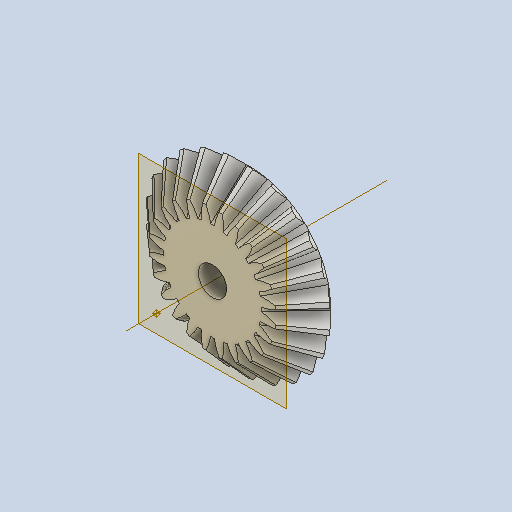
# Autodesk Inventor part: Bevel Gear1
Saved by Autodesk Inventor 2026.3 (Build 303398000, 398)
## iProperties
CustomPartVersion: 1
Created: 2026-10-19
Part Number: Bevel Gear1
Material: Steel, Mild
Document SubType Name: Modeling
Designer: Salim
Categories: <?xml version="1.0" encoding="UTF-16"?> <MemberInstance><Categories><FamilyTemplate><FamilyTemplateParameter ValueType="xs:double" Id="1" ObjectReferenceKey="da_z" ObjectType="kUserParameterObject"/><FamilyTemplateParameter ValueType="xs:double" Id="2" ObjectReferenceKey="da_b" ObjectType="kUserParameterObject"/><FamilyTemplateParameter ValueType="xs:double" Id="3" ObjectReferenceKey="da_beta" ObjectType="kUserParameterObject"/><FamilyTemplateParameter ValueType="xs:double" Id="4" ObjectReferenceKey="da_dae" ObjectType="kUserParameterObject"/><FamilyTemplateParameter ValueType="xs:double" Id="5" ObjectReferenceKey="da_ve" ObjectType="kUserParameterObject"/><FamilyTemplateParameter ValueType="xs:double" Id="6" ObjectReferenceKey="da_omega" ObjectType="kUserParameterObject"/><FamilyTemplateParameter ValueType="xs:string" Id="7" ObjectReferenceKey="EAIAABAAAAAAHwAAAAAAAIAAAAAAAAAA" ObjectType="83914240" SubObjectId="SurfaceGeometry"/></FamilyTemplate><ParamToTemplateMap><ParamToTemplate CategoryParameter="//CategoryParameter[@InternalName='046C89C9-8512-4d59-83FE-43B91F4F132A']" TemplateParameter="1"/><ParamToTemplate CategoryParameter="//CategoryParameter[@InternalName='2552DF32-E462-4b46-AEBF-C6C7768E72AC']" TemplateParameter="2"/><ParamToTemplate CategoryParameter="//CategoryParameter[@InternalName='C9EE641D-15FC-4fae-A226-E94C4372FDD7']" TemplateParameter="3"/><ParamToTemplate><ParamToTemplate CategoryParameter="//CategoryParameter[@InternalName='00B6519A-459B-49c7-AD84-2E56D39A5744']" ConstantValue="0.000000"/></ParamToTemplate><ParamToTemplate><ParamToTemplate CategoryParameter="//CategoryParameter[@InternalName='04B31F0E-C7A6-4894-AA32-9629BEFACF47']" ConstantValue="1.000000"/></ParamToTemplate><ParamToTemplate><ParamToTemplate CategoryParameter="//CategoryParameter[@InternalName='43CBEC2E-7847-49e7-A936-2F7889FCB2D9']" ConstantValue="0.200000"/></ParamToTemplate><ParamToTemplate><ParamToTemplate CategoryParameter="//CategoryParameter[@InternalName='B1EFC894-105D-4ebd-86BF-FA20ED196853']" ConstantValue="0.300000"/></ParamToTemplate><ParamToTemplate><ParamToTemplate CategoryParameter="//CategoryParameter[@InternalName='51175063-3D10-4879-93E8-6246FE8B403D']" ConstantValue="2060000000.000000"/></ParamToTemplate><ParamToTemplate><ParamToTemplate CategoryParameter="//CategoryParameter[@InternalName='A3A52E27-4454-46a9-B0BD-C932399B70AF']" ConstantValue="0.300000"/></ParamToTemplate><ParamToTemplate CategoryParameter="//CategoryParameter[@InternalName='2A200944-5A8C-41ca-B96E-8520D2E510F1']" TemplateParameter="4"/><ParamToTemplate><ParamToTemplate CategoryParameter="//CategoryParameter[@InternalName='1A637F62-92C8-44bc-B81F-10802510B579']" ConstantValue="1.687379"/></ParamToTemplate><ParamToTemplate CategoryParameter="//CategoryParameter[@InternalName='B52DD4BE-6863-48fb-BF58-89EF6F9EC65C']" TemplateParameter="5"/><ParamToTemplate><ParamToTemplate CategoryParameter="//CategoryParameter[@InternalName='3956BFF2-84D2-457d-93C2-9B0613DEBA67']" ConstantValue="0.749793"/></ParamToTemplate><ParamToTemplate CategoryParameter="//CategoryParameter[@InternalName='739CFA02-461B-4bf8-8049-181FCAD8B28F']" TemplateParameter="6"/><ParamToTemplate><ParamToTemplate CategoryParameter="//CategoryParameter[@InternalName='A27E999F-E2CE-4481-8A2A-EBF499C4C3C5']" ConstantValue="0.000000"/></ParamToTemplate><ParamToTemplate><ParamToTemplate CategoryParameter="//CategoryParameter[@InternalName='9E1B4470-B2D3-4ff1-B813-535BB4CDF51A']" ConstantValue="3520000.000000"/></ParamToTemplate><ParamToTemplate><ParamToTemplate CategoryParameter="//CategoryParameter[@InternalName='F8452263-BFF6-458c-9FB1-07C4B99E95CD']" ConstantValue="11400000.000000"/></ParamToTemplate><ParamToTemplate><ParamToTemplate CategoryParameter="//CategoryParameter[@InternalName='3E3BB259-FD49-497f-8171-6EBC954A3479']" ConstantValue="2.000000"/></ParamToTemplate><ParamToTemplate CategoryParameter="//CategoryParameter[@InternalName='27C3BAF2-7550-4e4b-AE2C-0DB134B7D9B7']" TemplateParameter="7"/></ParamToTemplateMap><Category DisplayName="Gear" InternalName="DC85795E-93AB-48d5-8EEE-5A27447B64BD" Mnemonic="Gear"><CategoryParameter DisplayName="z" InternalName="046C89C9-8512-4d59-83FE-43B91F4F132A" Mnemonic="z"/><CategoryParameter DisplayName="b" InternalName="2552DF32-E462-4b46-AEBF-C6C7768E72AC" Mnemonic="b"/><CategoryParameter DisplayName="||b|" InternalName="C9EE641D-15FC-4fae-A226-E94C4372FDD7" Mnemonic="beta"/><CategoryParameter DisplayName="x" InternalName="00B6519A-459B-49c7-AD84-2E56D39A5744" Mnemonic="x"/><CategoryParameter DisplayName="a*" InternalName="04B31F0E-C7A6-4894-AA32-9629BEFACF47" Mnemonic="a"/><CategoryParameter DisplayName="c*" InternalName="43CBEC2E-7847-49e7-A936-2F7889FCB2D9" Mnemonic="c"/><CategoryParameter DisplayName="r|.f|*" InternalName="B1EFC894-105D-4ebd-86BF-FA20ED196853" Mnemonic="rf"/><CategoryParameter DisplayName="E" InternalName="51175063-3D10-4879-93E8-6246FE8B403D" Mnemonic="E"/><CategoryParameter DisplayName="||m|" InternalName="A3A52E27-4454-46a9-B0BD-C932399B70AF" Mnemonic="mi"/><Category DisplayName="BevelGear" InternalName="0C98F69A-0C2B-4791-B2FE-7691BB227E77" Mnemonic="BevelGear"><CategoryParameter DisplayName="d|.ae|" InternalName="2A200944-5A8C-41ca-B96E-8520D2E510F1" Mnemonic="dae"/><CategoryParameter DisplayName="d|.ai|" InternalName="1A637F62-92C8-44bc-B81F-10802510B579" Mnemonic="dai"/><CategoryParameter DisplayName="A|.e|" InternalName="B52DD4BE-6863-48fb-BF58-89EF6F9EC65C" Mnemonic="ve"/><CategoryParameter DisplayName="A|.i|" InternalName="3956BFF2-84D2-457d-93C2-9B0613DEBA67" Mnemonic="vi"/><CategoryParameter DisplayName="||S|" InternalName="739CFA02-461B-4bf8-8049-181FCAD8B28F" Mnemonic="omega"/><CategoryParameter DisplayName="x|.t|" InternalName="A27E999F-E2CE-4481-8A2A-EBF499C4C3C5" Mnemonic="xt"/><CategoryParameter DisplayName="||s||.Flim|" InternalName="9E1B4470-B2D3-4ff1-B813-535BB4CDF51A" Mnemonic="sFlim"/><CategoryParameter DisplayName="||s||.Hlim|" InternalName="F8452263-BFF6-458c-9FB1-07C4B99E95CD" Mnemonic="sHlim"/><CategoryParameter DisplayName="type" InternalName="3E3BB259-FD49-497f-8171-6EBC954A3479" Mnemonic="type"/><CategoryParameter DisplayName="PitchDiameter" InternalName="27C3BAF2-7550-4e4b-AE2C-0DB134B7D9B7" Mnemonic="IDS_PITCHDIAM"/></Category></Category></Categories></MemberInstance>
Mass: 60.9118 g
Surface Area: 34.3074 cm^2
Volume: 7.7496 cm^3
Density: 7.86 g/cm^3
Appearance: Steel
d48: 0,000 mm
d49: 0,000 mm
d50: 90,00 deg
d52: 0,000 mm
d53: 0,000 mm
d54: 0,00 deg
Author: Salim
Autodesk Inventor part; units mm, degrees
ref_plane "Mesh Plane2" through (0, 0, 0) normal (0.9914449, 0.1305262, 0) x (0, 0, 1)
sketch "Teeth Body Sketch" plane through (0, 0, 0) normal (1, 0, 0) x (0, 1, 0)
  line L0 (0, 0) -> (12.2666, -14.1334) construction
  line L1 (12.2666, -14.1334) -> (13.9778, -12.4222)
  line L2 (13.9778, -12.4222) -> (0, 0) construction
  line L3 (13.2, -13.2) -> (0, 0) construction
  line L4 (7.404, -8.5308) -> (8.4369, -7.4979)
  line L5 (12.2666, -14.1334) -> (7.404, -8.5308)
  line L6 (13.9778, -12.4222) -> (8.4369, -7.4979)
  line L7 (0, -18.5019) -> (0, 3.0836) projected
  line L8 (0, -13.2) -> (13.9778, -13.2) construction
  dimension "d0" = 26.4
  dimension "d1" = 24.5332
  dimension "d2" = 27.9556
  dimension "d3" = 7.4
  dimension "d4" = 12.4222
  constraints: 16 end point, 4 point on line, 3 perpendicular, 2 collinear, 1 horizontal alignment, 1 vertical alignment
  measures "d0" diameter of L3.start L7
  measures "d1" diameter of L0.end L7
  measures "d2" diameter of L1.end L7
  measures "d3" distance between parallel lines of L1 L4
  measures "d4" vertical distance of L1.end L0.start
revolve "Teeth Body" add sketch "Teeth Body Sketch" angle 360 about axis through (0, 0, 0) along (0, 0, 1)
ref_plane "Tooth Plane" through (0, 13.2, -13.2) normal (0, -0.7071068, 0.7071068) x (1, 0, 0)
sketch "Start Sketch" plane through (0, 13.2, -13.2) normal (0, -0.7071068, 0.7071068) x (1, 0, 0)
  line L0 (0, -24.8388) -> (0, 6.4799) projected
  arc A0 (-0.4251, -1.6104) -> (-1.9482, 1.7332) centre (-7.1078, -2.6359) ccw
  arc A1 (1.9482, 1.7332) -> (0.4251, -1.6104) centre (7.1078, -2.6359) ccw
  line L1 (-0.4251, -1.6104) -> (0.4251, -1.6104)
  arc A2 (1.9482, 1.7332) -> (-1.9482, 1.7332) centre (0, -18.6676) ccw
  dimension "d7" = 6.7609
  dimension "d8" = 7.1078
  dimension "d9" = 16.0317
  dimension "d57" = 20.4936
  dimension "d58" = 17.0572
  constraints: 6 point on circle, 3 centre point, 3 symmetric about line, 2 end point, 1 coincident, 1 perpendicular, 1 other
  measures "d7" radius of A0
  measures "d8" horizontal distance of point (0, -18.668) A0.centre
  measures "d9" vertical distance of point (0, -18.668) A0.centre
  measures "d57" radius of A2
  measures "d58" distance from line of A2.centre L1
sketch "End Sketch" plane through (0, 7.8818, -7.8818) normal (0, -0.7071068, 0.7071068) x (1, 0, 0)
  line L0 (0, -14.7982) -> (0, 3.8605) projected
  arc A0 (-0.2538, -0.9616) -> (-1.1633, 1.0349) centre (-4.2441, -1.5739) ccw
  arc A1 (1.1633, 1.0349) -> (0.2538, -0.9616) centre (4.2441, -1.5739) ccw
  line L1 (-0.2538, -0.9616) -> (0.2538, -0.9616)
  arc A2 (1.1633, 1.0349) -> (-1.1633, 1.0349) centre (0, -11.1466) ccw
  dimension "d12" = 4.037
  dimension "d15" = 4.2441
  dimension "d16" = 9.5727
  dimension "d59" = 12.2369
  dimension "d60" = 10.185
  constraints: 6 point on circle, 3 centre point, 3 symmetric about line, 2 end point, 1 coincident, 1 other
  measures "d12" radius of A0
  measures "d15" horizontal distance of A0.centre point (0, -11.147)
  measures "d16" vertical distance of A0.centre point (0, -11.147)
  measures "d59" radius of A2
  measures "d60" distance from line of A2.centre L1
loft "Loft" cut profiles "Start Sketch", "End Sketch"
pattern_circular "Circular Pattern" count 24 over 360 about axis through (0, 0, 0) along (0, 0, 1) of "Loft"
ref_plane "End Plane" through (0, 7.8818, -7.8818) normal (0, -0.7071068, 0.7071068) x (1, 0, 0)
sketch3d "3D Sketch Right"
ref_plane "End Plane Right" through (-0.6296, 7.8567, -7.8818) normal (0.0564844, -0.7048472, 0.7071068) x (0.9968044, 0.079881, 0)
sketch "End Sketch Right" plane through (-0.6296, 7.8567, -7.8818) normal (0.0564844, -0.7048472, 0.7071068) x (0.9968044, 0.079881, 0)
  arc A0 (-0.2538, -0.9616) -> (-1.1633, 1.0349) centre (-4.2441, -1.5739) ccw
  line L0 (0, -15.5265) -> (0, 4.5888) projected
  arc A1 (1.1633, 1.0349) -> (0.2538, -0.9616) centre (4.2441, -1.5739) ccw
  line L1 (-0.2538, -0.9616) -> (0.2538, -0.9616)
  arc A2 (1.1633, 1.0349) -> (-1.1633, 1.0349) centre (0, -11.1466) ccw
  dimension "d70" = 4.2441
  dimension "d71" = 9.5727
  dimension "d72" = 4.037
  dimension "d73" = 10.185
  dimension "d74" = 12.2369
  constraints: 6 point on circle, 3 centre point, 3 symmetric about line, 2 end point, 1 coincident, 1 perpendicular, 1 other
  measures "d70" horizontal distance of A2.centre A0.centre
  measures "d71" vertical distance of point (0, -11.147) A0.centre
  measures "d72" radius of A0
  measures "d73" distance from line of point (0, -11.147) L1
  measures "d74" radius of A2
feature "Loft Right" [suppressed]
pattern_circular "Circular Pattern Right" [suppressed]
sketch3d "3D Sketch Left"
ref_plane "End Plane Left" through (0.6478, 7.8567, -7.884) normal (-0.0581021, -0.7046837, 0.7071387) x (0.9966181, -0.0821725, 0)
sketch "End Sketch Left" plane through (0.6478, 7.8567, -7.884) normal (-0.0581021, -0.7046837, 0.7071387) x (0.9966181, -0.0821725, 0)
  line L0 (0, -16.4458) -> (0, 5.3765) projected
  arc A0 (-0.2538, -0.9611) -> (-1.1633, 1.0354) centre (-4.2441, -1.5734) ccw
  arc A1 (1.1633, 1.0354) -> (0.2538, -0.9611) centre (4.2441, -1.5734) ccw
  line L1 (-0.2538, -0.9611) -> (0.2538, -0.9611)
  ellipse E0 centre (0, -5.3016) end of major axis (8.4369, -5.3016) minor radius 5.9661 projected
  arc A2 (1.1633, 1.0354) -> (-1.1633, 1.0354) centre (0, -11.1461) ccw
  dimension "d56" = 5.9661
  dimension "d30" = 4.037
  dimension "d31" = 4.2441
  dimension "d32" = 9.5727
  dimension "d61" = 12.2369
  dimension "d62" = 10.185
  constraints: 6 point on circle, 3 centre point, 3 symmetric about line, 2 end point, 1 coincident, 2 other
  measures "d30" radius of A0
  measures "d31" horizontal distance of point (0, -11.146) A0.centre
  measures "d32" vertical distance of A0.centre point (0, -11.146)
  measures "d61" radius of A2
  measures "d62" distance from line of point (0, -11.146) L1
feature "Loft Left" [suppressed]
pattern_circular "Circular Pattern Left" [suppressed]
sketch "Body Sketch" plane through (0, 0, 0) normal (1, 0, 0) x (0, 1, 0)
  line L0 (0, -16.6447) -> (0, -8.0592) projected
  line L1 (12.2666, -14.1334) -> (7.404, -8.5308) projected
  line L2 (7.404, -8.5308) -> (0, -8.5308)
  line L3 (12.2666, -14.1334) -> (0, -14.1334)
  constraints: 4 end point, 2 perpendicular, 2 point on line
revolve "Fix Body" add sketch "Body Sketch" angle 360 about axis through (0, 0, 0) along (0, 0, 1)
sketch "Sketch6" plane through (0, 0, 0) normal (1, 0, 0) x (0, 1, 0)
  line L0 (13.2, -13.2) -> (0, 0) projected
  line L1 (0, -17.28) -> (0, 2.88) projected
surface revolve "Pitch Diameter" sketch "Sketch6" angle 360 about axis through (0, 0, 0) along (0, 0, 1) shown no curves L0
ref_plane "Work Plane6" through (0, 0, -8.5308) normal (0, 0, 1) x (1, 0, 0)
split "Split1" plane through (0, 0, -8.5308) removes the side toward (0, 0, 1)
sketch "Sketch8" plane through (0.5977, 8.486, -8.5308) normal (0, 0, 1) x (0.8984768, -0.439021, 0)
  circle A0 centre (3.1885, -7.8869) radius 2.15
  dimension "d95" = 4.3
  constraints: 1 centre point, 1 coincident
  measures "d95" diameter of A0
extrude "Extrusion1" cut sketch "Sketch8" against normal blind 10
equation "\"d0\" = da_de"
equation "\"d1\" = da_dfe"
equation "\"d2\" = da_dae"
equation "\"d3\" = da_b"
equation "\"d4\" = da_ve"
equation "\"d7\" = fd_rr"
equation "\"d8\" = fd_x"
equation "\"d9\" = fd_y"
equation "\"d57\" = 0.5 * fd_dva + 0.3 * da_he"
equation "\"d58\" = 0.5 * fd_dva - 1.12 * da_he"
equation "\"da_teethtype\" = 0"
equation "\"da_b\" = 7.4"
equation "\"da_de\" = 26.4"
equation "\"da_dae\" = 27.95563"
equation "\"da_dfe\" = 24.53324"
equation "\"da_le\" = 18.66762"
equation "\"da_omega\" = 90deg"
equation "\"da_beta\" = 0"
equation "\"da_delta\" = 45deg"
equation "\"da_alpha\" = 20deg"
equation "\"da_he\" = 2.42"
equation "\"da_ve\" = 12.42218"
equation "\"da_zv\" = 33.941125"
equation "\"fd_loft\" = da_b + 0.05 * da_he"
equation "\"fd_x\" = fd_x1 + fd_x2"
equation "\"fd_y\" = fd_y1 - fd_y2"
equation "\"fd_dd\" = fd_dva - 0.8 * da_he"
equation "\"da_dvw\" = 37.33524"
equation "\"d11\" = fd_loft"
equation "\"da_dm\" = 21.16741"
equation "\"da_x\" = 0"
equation "\"da_m\" = 1.1"
equation "\"d50\" = da_omega"
equation "\"fd_rr\" = 6.760924"
equation "\"fd_dva\" = 39.535238"
equation "\"fd_x1\" = 0.873219"
equation "\"fd_x2\" = 6.234536"
equation "\"fd_y1\" = 18.647184"
equation "\"fd_y2\" = 2.615464"
body "Solid1"
body "Srf1"
